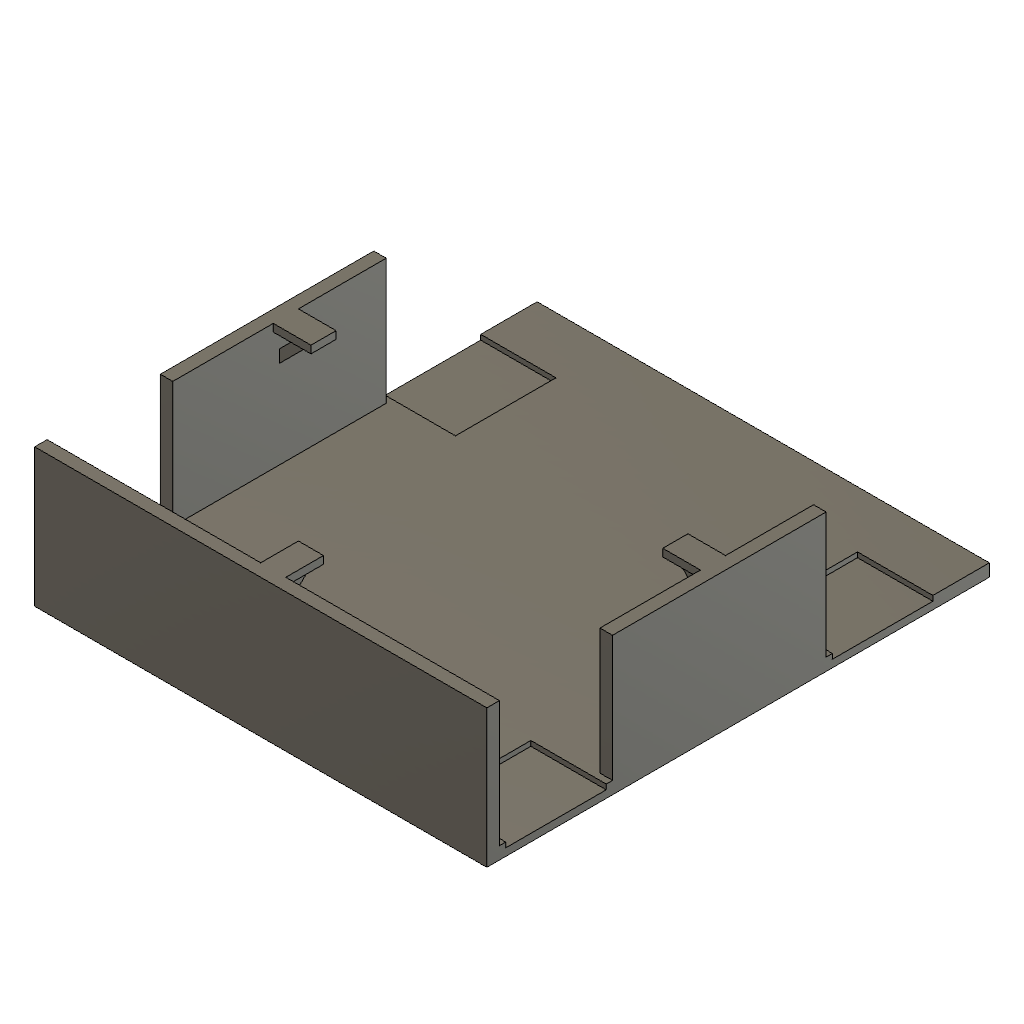
Robo Soccer(BASE) (Autodesk Fusion 360 design; units mm, degrees)
part number: 2026-11-05-15-55-35-834
Autodesk Fusion 360 part; units mm, degrees
sketch "Sketch1" plane through (0, 0, 0) normal (0, 1, 0) x (1, 0, 0)
  line L0 (-90, 100) -> (90, 100)
  line L1 (90, 100) -> (90, -100)
  line L2 (90, -100) -> (-90, -100)
  line L3 (-90, -100) -> (-90, 100)
  line L4 (-90, 100) -> (-90, 80)
  line L5 (-90, -50) -> (-85, -50)
  line L6 (-85, -50) -> (-85, 35)
  line L7 (-85, 35) -> (-90, 35)
  line L8 (-90, 35) -> (-90, -50)
  line L9 (90, 35) -> (85, 35)
  line L10 (85, 35) -> (85, -50)
  line L11 (85, -50) -> (90, -50)
  line L12 (90, -50) -> (90, 35)
  line L13 (-90, -95) -> (90, -95)
  line L14 (90, -95) -> (90, -100)
  line L15 (90, -100) -> (-90, -100)
  line L16 (-90, -100) -> (-90, -95)
  dimension "d1" = 180
  dimension "d2" = 200
  constraint horizontal L0
  constraint vertical L1
  constraint horizontal L2
  constraint vertical L3
  constraint coincident L3 L4.end
  constraint horizontal L5
  constraint vertical L6
  constraint horizontal L7
  constraint vertical L8
  constraint coincident L3 L5.start
  constraint horizontal L9
  constraint vertical L10
  constraint horizontal L11
  constraint vertical L12
  constraint coincident L1 L9.start
  constraint horizontal L13
  constraint vertical L14
  constraint horizontal L15
  constraint vertical L16
  constraint coincident L3 L13.start
  measures "d1" distance of L0.start L0.end
  measures "d2" distance of L0.start L2.end
extrude "Extrude1" add sketch "Sketch1" along normal blind 5 contours L0 L1 L3 L4 L5 L6 L7 L9 L10 L11 L13 makes body 1
extrude "Extrude2" add sketch "Sketch1" along normal blind 55 contours L1 L9 L10 L11 L12 | L3 L5 L6 L7 L8 | L1 L2 L3 L13 L14 L15 L16 bodies 1
sketch "Sketch2" plane through (0, 0, 100) normal (0, 0, 1) x (1, 0, 0)
  line L0 (-90, 0) -> (90, 0)
  line L1 (90, 0) -> (90, 55)
  line L2 (90, 55) -> (-90, 55)
  line L3 (-90, 55) -> (-90, 0)
  line L4 (-4, 45) -> (4, 45)
  line L5 (4, 45) -> (4, 40)
  line L6 (4, 40) -> (-4, 40)
  line L7 (-4, 40) -> (-4, 45)
  constraint horizontal L4
  constraint vertical L5
  constraint horizontal L6
  constraint vertical L7
extrude "Extrude3" cut sketch "Sketch2" against normal blind 5 contours L4 L5 L6 L7 bodies 1
sketch "Sketch3" plane through (-90, 0, 0) normal (-1, 0, 0) x (0, 0, 1)
  line L0 (-100, 0) -> (100, 0)
  line L1 (100, 0) -> (100, 55)
  line L2 (100, 55) -> (95, 55)
  line L3 (95, 55) -> (95, 5)
  line L4 (95, 5) -> (50, 5)
  line L5 (50, 5) -> (50, 55)
  line L6 (50, 55) -> (-35, 55)
  line L7 (-35, 55) -> (-35, 5)
  line L8 (-35, 5) -> (-100, 5)
  line L9 (-100, 5) -> (-100, 0)
  line L10 (52.5, 5) -> (92.5, 5)
  line L11 (92.5, 5) -> (92.5, 3)
  line L12 (92.5, 3) -> (52.5, 3)
  line L13 (52.5, 3) -> (52.5, 5)
  constraint horizontal L10
  constraint vertical L11
  constraint horizontal L12
  constraint vertical L13
  constraint coincident L4 L10.start
extrude "Extrude4" cut sketch "Sketch3" against normal blind 30 contours L4 L10 L11 L12 L13 bodies 1
sketch "Sketch4" plane through (-90, 0, 0) normal (-1, 0, 0) x (0, 0, 1)
  line L0 (52.5, 3) -> (52.5, 5)
  line L1 (52.5, 5) -> (50, 5)
  line L2 (50, 5) -> (50, 55)
  line L3 (50, 55) -> (-35, 55)
  line L4 (-35, 55) -> (-35, 5)
  line L5 (-35, 5) -> (-100, 5)
  line L6 (-100, 5) -> (-100, 0)
  line L7 (-100, 0) -> (100, 0)
  line L8 (100, 0) -> (100, 55)
  line L9 (100, 55) -> (95, 55)
  line L10 (95, 55) -> (95, 5)
  line L11 (95, 5) -> (92.5, 5)
  line L12 (92.5, 5) -> (92.5, 3)
  line L13 (92.5, 3) -> (52.5, 3)
  line L14 (-37.5, 5) -> (-77.5, 5)
  line L15 (-77.5, 5) -> (-77.5, 3)
  line L16 (-77.5, 3) -> (-37.5, 3)
  line L17 (-37.5, 3) -> (-37.5, 5)
  dimension "d11" = 40
  dimension "d12" = 2
  constraint horizontal L14
  constraint vertical L15
  constraint horizontal L16
  constraint vertical L17
  constraint coincident L5 L14.start
  measures "d11" distance of L14.start L14.end
  measures "d12" distance of L14.start L16.end
extrude "Extrude5" cut sketch "Sketch4" against normal blind 30 contours L5 L14 L15 L16 L17 bodies 1
sketch "Sketch5" plane through (90, 0, 0) normal (1, 0, 0) x (0, 0, -1)
  line L0 (-100, 0) -> (100, 0)
  line L1 (100, 0) -> (100, 5)
  line L2 (100, 5) -> (35, 5)
  line L3 (35, 5) -> (35, 55)
  line L4 (35, 55) -> (-50, 55)
  line L5 (-50, 55) -> (-50, 5)
  line L6 (-50, 5) -> (-95, 5)
  line L7 (-95, 5) -> (-95, 55)
  line L8 (-95, 55) -> (-100, 55)
  line L9 (-100, 55) -> (-100, 0)
  line L10 (-92.5, 5) -> (-52.5, 5)
  line L11 (-52.5, 5) -> (-52.5, 3)
  line L12 (-52.5, 3) -> (-92.5, 3)
  line L13 (-92.5, 3) -> (-92.5, 5)
  dimension "d15" = 40
  dimension "d16" = 2
  constraint horizontal L10
  constraint vertical L11
  constraint horizontal L12
  constraint vertical L13
  constraint coincident L6 L10.start
  measures "d15" distance of L10.start L10.end
  measures "d16" distance of L10.start L12.end
extrude "Extrude6" cut sketch "Sketch5" against normal blind 30 contours L6 L10 L11 L12 L13 bodies 1
sketch "Sketch6" plane through (90, 0, 0) normal (1, 0, 0) x (0, 0, -1)
  line L0 (-92.5, 3) -> (-92.5, 5)
  line L1 (-92.5, 5) -> (-95, 5)
  line L2 (-95, 5) -> (-95, 55)
  line L3 (-95, 55) -> (-100, 55)
  line L4 (-100, 55) -> (-100, 0)
  line L5 (-100, 0) -> (100, 0)
  line L6 (100, 0) -> (100, 5)
  line L7 (100, 5) -> (35, 5)
  line L8 (35, 5) -> (35, 55)
  line L9 (35, 55) -> (-50, 55)
  line L10 (-50, 55) -> (-50, 5)
  line L11 (-50, 5) -> (-52.5, 5)
  line L12 (-52.5, 5) -> (-52.5, 3)
  line L13 (-52.5, 3) -> (-92.5, 3)
  line L14 (37.5, 5) -> (77.5, 5)
  line L15 (77.5, 5) -> (77.5, 3)
  line L16 (77.5, 3) -> (37.5, 3)
  line L17 (37.5, 3) -> (37.5, 5)
  dimension "d19" = 40
  dimension "d20" = 2
  constraint horizontal L14
  constraint vertical L15
  constraint horizontal L16
  constraint vertical L17
  constraint coincident L7 L14.start
  measures "d19" distance of L14.start L14.end
  measures "d20" distance of L14.start L16.end
extrude "Extrude7" cut sketch "Sketch6" against normal blind 30 contours L7 L14 L15 L16 L17 bodies 1
sketch "Sketch7" plane through (0, 0, 0) normal (1, 0, 0) x (0, 0, -1)
  line L0 (-95, 55) -> (-75, 55)
  line L1 (-75, 55) -> (-75, 52)
  line L2 (-75, 52) -> (-95, 52)
  line L3 (-95, 52) -> (-95, 55)
  line L4 (-95, 40) -> (-83, 52)
  line L5 (-95, 45) -> (-88, 52)
  line L6 (-95, 40) -> (-95, 45)
  line L7 (-80, 55) -> (-80, 52)
  constraint horizontal L0
  constraint perpendicular L0 L1
  constraint perpendicular L1 L2
  constraint perpendicular L0 L3
  constraint coincident L2 L4.end
  constraint coincident L2 L5.end
  constraint parallel L4 L5
  constraint vertical L6
  constraint coincident L0 L7.start
  constraint coincident L2 L7.end
  constraint perpendicular L2 L7
extrude "Extrude8" add sketch "Sketch7" along normal blind 5 contours L0 L2 L3 L7 bodies 1
extrude "Extrude9" add sketch "Sketch7" against normal blind 5 contours L0 L2 L3 L7 bodies 1
extrude "Extrude10" add sketch "Sketch7" along normal blind 3 separate body contours L2 L4 L5 L6 makes body 2
extrude "Extrude11" add sketch "Sketch7" against normal blind 3 contours L2 L4 L5 L6 bodies 1 2
extrude "Extrude12" add 1 faces at (1, 40, 98.3333) along direction (0, 1, 0) blind 5 on bodies 1 bodies 1
sketch "Sketch9" plane through (0, 0, 0) normal (0, 0, 1) x (1, 0, 0)
  line L0 (85, 55) -> (70, 55)
  line L1 (70, 55) -> (70, 52)
  line L2 (70, 52) -> (85, 52)
  line L3 (85, 52) -> (85, 55)
  line L4 (85, 45) -> (78, 52)
  line L5 (85, 40) -> (73, 52)
  line L6 (85, 45) -> (85, 40)
  constraint horizontal L0
  constraint vertical L1
  constraint horizontal L2
  constraint vertical L3
  constraint coincident L2 L4.end
  constraint coincident L2 L5.end
  constraint parallel L4 L5
  constraint perpendicular L2 L6
extrude "Extrude13" add sketch "Sketch9" along normal blind 10 contours L0 L1 L2 L3 bodies 1
extrude "Extrude14" add sketch "Sketch9" along normal blind 7.5 contours L2 L4 L5 L6 bodies 1
extrude "Extrude15" cut sketch "Sketch9" along normal blind 2.5 contours L2 L4 L5 L6 bodies 1
sketch "Sketch10" plane through (0, 0, 0) normal (0, 0, 1) x (1, 0, 0)
  line L0 (-85, 55) -> (-70, 55)
  line L1 (-70, 55) -> (-70, 52)
  line L2 (-70, 52) -> (-85, 52)
  line L3 (-85, 52) -> (-85, 55)
  line L4 (-85, 45) -> (-78, 52)
  line L5 (-85, 40) -> (-73, 52)
  line L6 (-85, 40) -> (-85, 45)
  constraint horizontal L0
  constraint vertical L1
  constraint horizontal L2
  constraint vertical L3
  constraint coincident L2 L4.end
  constraint coincident L2 L5.end
  constraint parallel L4 L5
  constraint perpendicular L2 L6
extrude "Extrude16" add sketch "Sketch10" along normal blind 10 contours L0 L1 L2 L3 bodies 1
extrude "Extrude17" add sketch "Sketch10" along normal blind 7.5 contours L2 L4 L5 L6 bodies 1
extrude "Extrude18" cut sketch "Sketch10" along normal blind 2.5 contours L2 L4 L5 L6 bodies 1
